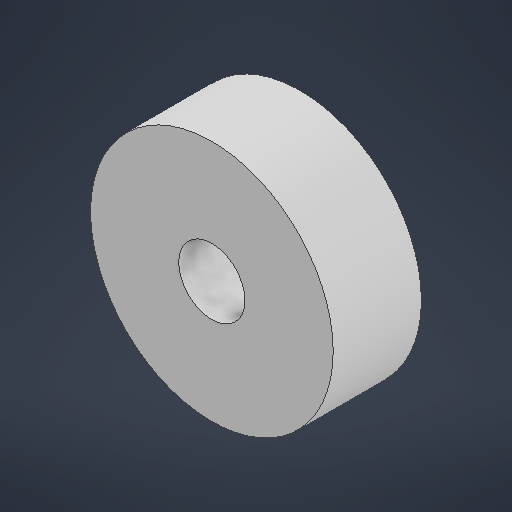
# Autodesk Inventor part: kolo
Saved by Autodesk Inventor 2027.2 (Build 312334000, 334)
## iProperties
Created: 2026-11-18
Part Number: kolo
Material: Generic
Document SubType Name: Modeling
Designer: dodo
Density: 1 g/cm^3
Appearance: Default
Author: dodo
Autodesk Inventor part; units mm, degrees
ref_plane "YZ Plane" through (0, 0, 0) normal (1, 0, 0) x (0, 1, 0)
ref_plane "XZ Plane" through (0, 0, 0) normal (0, 1, 0) x (-1, 0, 0)
ref_plane "XY Plane" through (0, 0, 0) normal (0, 0, 1) x (1, 0, 0)
sketch "Sketch1" plane through (0, 0, 0) normal (0, 0, 1) x (1, 0, 0)
  circle A0 centre (0, 0) radius 5.5
  dimension "d0" = 11
  constraints: 2 coincident, 1 centre point
  measures "d0" diameter of A0
sketch "Sketch2" plane through (0, 0, 0) normal (0, 0, 1) x (1, 0, 0)
  circle A0 centre (0, 0) radius 1.5
  dimension "d1" = 3
  constraints: 1 centre point, 1 coincident
  measures "d1" diameter of A0
extrude "Extrusion1" add sketch "Sketch1" against normal blind 4
extrude "Extrusion2" cut sketch "Sketch2" against normal blind 3
body "Solid1"
